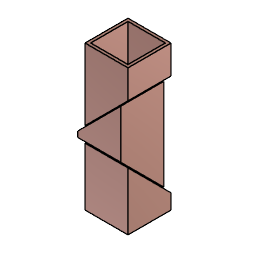
PDP_Lamp_Assembly (Autodesk Fusion 360 design; units mm, degrees)
Autodesk Fusion 360 part; units mm, degrees
sketch "Sketch1" plane through (0, 0, 0) normal (0, 0, 1) x (1, 0, 0)
  line L0 (75, 75) -> (-75, 75)
  line L1 (-75, 75) -> (-75, -75)
  line L2 (-75, -75) -> (75, -75)
  line L3 (75, -75) -> (75, 75)
  line L4 (75, 75) -> (-75, -75) construction
  line L5 (-75, 75) -> (75, -75) construction
  line L6 (-65, -65) -> (65, -65)
  line L7 (65, -65) -> (65, 65)
  line L8 (65, 65) -> (-65, 65)
  line L9 (-65, 65) -> (-65, -65)
  dimension "d1" = 150
  dimension "d2" = 150
  dimension "d3" = -10
  constraint horizontal L0
  constraint perpendicular L0 L1
  constraint parallel L0 L2
  constraint parallel L1 L3
  constraint coincident L4 origin
  constraint coincident L5 origin
  measures "d1" distance of L1.end L2.end
  measures "d2" distance of L0.end L1.end
extrude "Extrude1" add sketch "Sketch1" along normal blind 500 makes body 1
ref_plane "WorkPlane1" through (12.125, 0, 0) normal (0, 0.707107, 0.707107) x (1, 0, 0)
ref_plane "WorkPlane2" through (12.125, 70.7107, 70.7107) normal (0, 0.707107, 0.707107) x (1, 0, 0)
sketch "Sketch2" plane through (0, 70.7107, 70.7107) normal (0, 0.707107, 0.707107) x (1, 0, 0)
  line L0 (317.6471, -300) -> (-317.6471, -300)
  line L1 (-317.6471, -300) -> (-317.6471, 300)
  line L2 (-317.6471, 300) -> (317.6471, 300)
  line L3 (317.6471, 300) -> (317.6471, -300)
  line L4 (317.6471, -300) -> (-317.6471, 300) construction
  line L5 (-317.6471, -300) -> (317.6471, 300) construction
  dimension "d8" = 600
  constraint horizontal L0
  constraint perpendicular L0 L1
  constraint parallel L0 L2
  constraint parallel L1 L3
  constraint coincident L4 origin
  constraint coincident L5 origin
  measures "d8" distance of L0.start L2.end
extrude "Extrude2" cut sketch "Sketch2" against normal blind 10 bodies 1 makes body 2 at (-25, -75, 134.8528)
ref_plane "WorkPlane3" through (0, 12.125, 0) normal (-0.707107, 0, 0.707107) x (0, 1, 0)
ref_plane "WorkPlane4" through (-162.6346, 12.125, 162.6346) normal (-0.707107, 0, 0.707107) x (0, 1, 0)
sketch "Sketch3" plane through (-162.6346, 0, 162.6346) normal (-0.707107, 0, 0.707107) x (0, 1, 0)
  line L0 (-263.4399, -400) -> (263.4399, -400)
  line L1 (263.4399, -400) -> (263.4399, 400)
  line L2 (263.4399, 400) -> (-263.4399, 400)
  line L3 (-263.4399, 400) -> (-263.4399, -400)
  line L4 (-263.4399, -400) -> (263.4399, 400) construction
  line L5 (263.4399, -400) -> (-263.4399, 400) construction
  dimension "d15" = 800
  constraint horizontal L0
  constraint perpendicular L0 L1
  constraint parallel L0 L2
  constraint parallel L1 L3
  constraint coincident L4 origin
  constraint coincident L5 origin
  measures "d15" distance of L0.end L1.end
extrude "Extrude3" cut sketch "Sketch3" against normal blind 10 bodies 1 2 makes body 3 at (75, 25, 222.9899)
sketch "Sketch7" plane through (0, 75, 0) normal (0, 1, 0) x (-1, 0, 0)
  line L0 (75, 236.127) -> (-75, 386.127)
  line L1 (-75, 386.127) -> (-75, 66.4214)
  line L2 (-75, 66.4214) -> (75, 66.4214)
  line L3 (75, 66.4214) -> (75, 236.127)
  line L4 (-75, 66.4214) -> (75, 66.4214)
  line L5 (-75, 66.4214) -> (-75, 386.127)
  line L6 (-66.2025, 66.4214) -> (-66.2025, 81.4214)
  line L7 (-66.2025, 81.4214) -> (63.7975, 81.4214)
  line L8 (63.7975, 81.4214) -> (63.7975, 66.4214)
  line L9 (63.7975, 66.4214) -> (-66.2025, 66.4214)
  dimension "d26" = 15
  dimension "d27" = 130
  constraint coincident L2 L6.start
  constraint perpendicular L2 L6
  constraint perpendicular L6 L7
  constraint coincident L4 L8.end
  constraint perpendicular L4 L8
  measures "d26" distance of L6.start L6.end
  measures "d27" distance of L6.end L7.end
extrude "Extrude7" cut sketch "Sketch7" against normal blind 10 contours L2 L4 L6 L7 L8 L9 bodies 3
sketch "Sketch9" plane through (-75, 0, 0) normal (-1, 0, 0) x (0, -1, 0)
  line L0 (-75, 250.2691) -> (75, 250.2691)
  line L1 (75, 250.2691) -> (75, 500)
  line L2 (75, 500) -> (-75, 500)
  line L3 (-75, 500) -> (-75, 250.2691)
  line L4 (-75, 250.2691) -> (75, 250.2691)
  line L5 (-75, 250.2691) -> (-75, 500)
  line L6 (-65, 250.2691) -> (-65, 265.2691)
  line L7 (-65, 265.2691) -> (65, 265.2691)
  line L8 (65, 265.2691) -> (65, 250.2691)
  line L9 (65, 250.2691) -> (-65, 250.2691)
  dimension "d34" = 15
  dimension "d35" = 10
  constraint coincident L0 L6.start
  constraint perpendicular L0 L6
  constraint perpendicular L6 L7
  constraint coincident L4 L8.end
  constraint perpendicular L4 L8
  measures "d34" distance of L6.start L6.end
  measures "d35" distance of L3 L6
extrude "Extrude9" cut sketch "Sketch9" against normal blind 10 contours L0 L4 L6 L7 L8 L9 bodies 1
move_body "Move1" bodies 3 1 to x (1, 0, 0) y (0, 1, 0) z (0, 0, 1) at (0, -25, 15)
move_body "Move2" bodies 1 to x (1, 0, 0) y (0, 1, 0) z (0, 0, 1) at (25, 0, 14)
